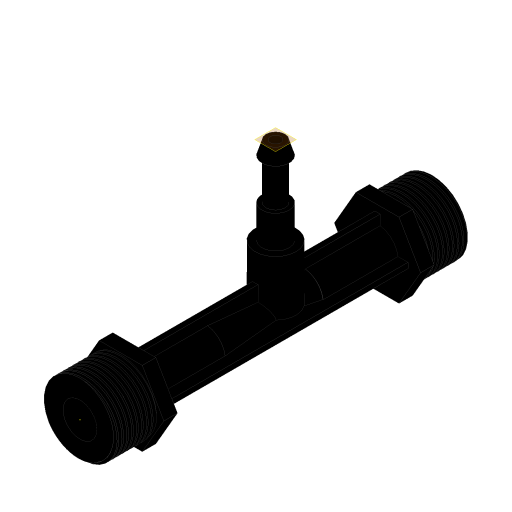
# Autodesk Inventor part: 0.75 Inch Venturi
Saved by Autodesk Inventor 2024 (Build 280153000, 153)
## iProperties
Created: 2024-08-13
Part Number: 0.75 Inch Venturi
Material: Generic
Document SubType Name: Modeling
Designer: nicme
Density: 1 g/cm^3
Appearance: Default
Author: nicme
Autodesk Inventor part; units mm, degrees
ref_plane "YZ Plane" through (0, 0, 0) normal (1, 0, 0) x (0, 1, 0)
sketch "Sketch1" plane through (0, 0, 0) normal (0, 0, 1) x (1, 0, 0)
  circle A0 centre (0, 0) radius 6.25
  circle A1 centre (0, 0) radius 13.22
  dimension "d0" = 12.5
  dimension "d1" = 26.44
  constraints: 2 centre point, 2 coincident
  measures "d0" diameter of A0
  measures "d1" diameter of A1
extrude "Extrusion1" add sketch "Sketch1" against normal blind 15
sketch "Sketch2" plane through (0, 0, 0) normal (1, 0, 0) x (0, 1, 0)
  line L0 (13.22, 0) -> (-13.22, 0) projected
  line L1 (13.22, 0) -> (12.058, 0.6049)
  line L2 (12.2284, 0.6936) -> (13.22, 1.2098)
  line L3 (13.22, 1.2098) -> (13.22, 0)
  line L4 (13.22, 0.6049) -> (11.3544, 0.6049) construction
  arc A0 (12.2284, 0.6936) -> (12.2284, 0.5162) centre (12.2746, 0.6049) ccw
  line L5 (0, 11.5896) -> (0, -31.834) construction
  point P0 (0, 0)
  dimension "d4" = 55
  dimension "d5" = 1.162
  dimension "d6" = 0.2
  constraints: 10 end point, 2 point on circle, 2 point on line, 2 tangent, 2 vertical, 1 centre point, 1 horizontal, 1 midpoint
  measures "d4" angle of L1 L2
  measures "d5" distance of L4.start L1.end
  measures "d6" diameter of A0
coil "Coil1" sketch "Sketch2" operation cut axis through (0, 0, 11.5896) along (0, 0, -1) pitch 1.814 turns 10 hand right
sketch "Sketch3" plane through (0, 0, -15) normal (0, 0, -1) x (-1, 0, 0)
  line L0 (-7.9386, 13.75) -> (7.9386, 13.75)
  line L1 (7.9386, 13.75) -> (15.8771, 0)
  line L2 (15.8771, 0) -> (7.9386, -13.75)
  line L3 (7.9386, -13.75) -> (-7.9386, -13.75)
  line L4 (-7.9386, -13.75) -> (-15.8771, 0)
  line L5 (-15.8771, 0) -> (-7.9386, 13.75)
  line L6 (-7.9386, 13.75) -> (7.9386, -13.75) construction
  line L7 (-7.9386, -13.75) -> (7.9386, 13.75) construction
  circle A0 centre (0, 0) radius 6.25
  point P0 (11.9078, 6.875)
  dimension "d15" = 27.5
  dimension "d16" = 120
  dimension "d17" = 120
  dimension "d18" = 120
  dimension "d19" = 120
  dimension "d20" = 120
  dimension "d21" = 120
  dimension "d22" = 27.5
  dimension "d24" = 27.5
  dimension "d25" = 13.75
  dimension "d26" = 13.75
  constraints: 16 end point, 2 coincident, 2 midpoint, 1 centre point, 1 horizontal, 1 parallel
  measures "d15" distance between parallel lines of L3 L0
  measures "d16" angle of L0 L5
  measures "d17" angle of L1 L0
  measures "d18" angle of L4 L5
  measures "d19" angle of L2 L1
  measures "d20" angle of L3 L4
  measures "d21" angle of L2 L3
  measures "d22" distance from line of point (11.908, 6.875) L4
  measures "d24" distance between parallel lines of L2 L5
  measures "d25" distance from line of L0 L4.end
  measures "d26" distance from line of L1 L2.end
extrude "Extrusion2" add sketch "Sketch3" along normal blind 5
sketch "Sketch4" plane through (0, 0, -20) normal (0, 0, -1) x (-1, 0, 0)
  circle A0 centre (0, 0) radius 6.2339
  circle A1 centre (0, 0) radius 7.5
  dimension "d29" = 15
  constraints: 2 centre point, 2 coincident
  measures "d29" diameter of A1
extrude "Extrusion3" add sketch "Sketch4" along normal blind 26
sketch "Sketch5" plane through (0, 0, -46) normal (0, 0, -1) x (-1, 0, 0)
  circle A0 centre (0, 0) radius 6.25
  circle A1 centre (0, 0) radius 7.5
  constraints: 2 centre point, 2 coincident
ref_plane "Work Plane1" through (0, 0, -72) normal (0, 0, -1) x (-1, 0, 0)
sketch "Sketch7" plane through (0, 0, -72) normal (0, 0, -1) x (-1, 0, 0)
  circle A0 centre (0, 0) radius 4
  circle A1 centre (0, 0) radius 5
  dimension "d39" = 8
  dimension "d40" = 10
  constraints: 2 centre point, 2 coincident
  measures "d39" diameter of A0
  measures "d40" diameter of A1
loft "Loft2" add profiles "Sketch7" section 1 edges at (7.5, 0, -46) contours A0 | A1
ref_plane "Work Plane2" through (0, 0, -82) normal (0, 0, -1) x (-1, 0, 0)
sketch "Sketch8" plane through (0, 0, -82) normal (0, 0, -1) x (-1, 0, 0)
  circle A0 centre (0, 0) radius 7.5
  constraints: 1 centre point, 1 coincident
loft "Loft3" add profiles "Sketch8" section 1 edges at (5, 0, -72)
sketch "Sketch9" plane through (0, 0, -82) normal (0, 0, -1) x (-1, 0, 0)
  circle A0 centre (0, 0) radius 7.6171
  constraints: 1 centre point, 1 coincident
extrude "Extrusion4" add sketch "Sketch9" along normal blind 27.5
sketch "Sketch10" plane through (0, 0, -109.5) normal (0, 0, -1) x (-1, 0, 0)
  line L0 (7.9386, 13.75) -> (-7.9386, 13.75) projected
  line L1 (-7.9386, 13.75) -> (-15.8771, 0) projected
  line L2 (-15.8771, 0) -> (-7.9386, -13.75) projected
  line L3 (-7.9386, -13.75) -> (7.9386, -13.75) projected
  line L4 (7.9386, -13.75) -> (15.8771, 0) projected
  line L5 (15.8771, 0) -> (7.9386, 13.75) projected
  point P0 (0, 0)
extrude "Extrusion5" add sketch "Sketch10" along normal blind 5
sketch "Sketch11" plane through (0, 0, -114.5) normal (0, 0, -1) x (-1, 0, 0)
  circle A0 centre (0, 0) radius 6.25 projected
  circle A1 centre (0, 0) radius 13.2205
  dimension "d54" = 26.441
  constraints: 1 centre point, 1 coincident
  measures "d54" diameter of A1
extrude "Extrusion6" add sketch "Sketch11" along normal blind 15
sketch "Sketch12" plane through (0, 0, 0) normal (1, 0, 0) x (0, 1, 0)
  line L0 (-13.2205, -129.5) -> (13.2205, -129.5) projected
  line L1 (13.2205, -129.5) -> (13.2205, -130.7098)
  line L2 (13.2205, -130.7098) -> (12.0585, -130.1049)
  line L3 (12.0585, -130.1049) -> (13.2205, -129.5)
  line L4 (13.2205, -130.1049) -> (11.3822, -130.1049) construction
  line L5 (0, -132.3571) -> (0, -126.5708) construction
  point P0 (0, 0)
  dimension "d57" = 55
  dimension "d58" = 1.162
  constraints: 10 end point, 2 vertical, 1 horizontal, 1 midpoint
  measures "d57" angle of L2 L3
  measures "d58" distance from line of L2.end L1
coil "Coil2" sketch "Sketch12" operation cut axis through (0, 0, -132.3571) along (0, 0, 1) pitch 1.814 turns 9 hand right
sketch "Sketch13" plane through (0, 0, -109.5) normal (0, 0, 1) x (1, 0, 0)
  line L0 (-1, -11.25) -> (1, -11.25)
  line L1 (1, -11.25) -> (1, 11.25)
  line L2 (1, 11.25) -> (-1, 11.25)
  line L3 (-1, 11.25) -> (-1, -11.25)
  circle A0 centre (0, 0) radius 6.25 projected
  line L4 (-1, -11.25) -> (1, 11.25) construction
  line L5 (1, -11.25) -> (-1, 11.25) construction
  line L6 (11.25, 1) -> (-11.25, 1)
  line L7 (-11.25, 1) -> (-11.25, -1)
  line L8 (-11.25, -1) -> (11.25, -1)
  line L9 (11.25, -1) -> (11.25, 1)
  line L10 (11.25, 1) -> (-11.25, -1) construction
  line L11 (-11.25, 1) -> (11.25, -1) construction
  point P0 (6.1695, 1)
  point P1 (6.1695, -1)
  point P2 (-1, -1)
  point P3 (-1, 1)
  point P4 (1, -1)
  point P5 (1, 1)
  dimension "d67" = 2
  dimension "d68" = 22.5
  dimension "d69" = 2
  dimension "d70" = 22.5
  constraints: 24 end point, 4 midpoint, 4 parallel, 2 horizontal, 2 perpendicular
  measures "d67" distance of L2.end L1.end
  measures "d68" distance of L8.end L7.end
  measures "d69" distance of L7.end L6.end
  measures "d70" distance between parallel lines of L0 L2
extrude "Extrusion7" add sketch "Sketch13" along normal up to surface (89.5 mm away) contours L3 A0 L1 L0 | L3 L8 L1 A0 | L8 A0 L6 L3 | L3 L6 L1 L8 | L8 L7 L6 A0 | L1 L6 A0 L8 | A0 L6 L9 L8 | L3 A0 L1 L6 | L3 L2 L1 A0
sketch "Sketch14" plane through (-1, 11.25, -109.5) normal (0, 1, 0) x (1, 0, 0)
  circle A0 centre (1, -37.5) radius 7.5
  point P0 (1, -109.5)
  dimension "d73" = 15
  constraints: 1 centre point
  measures "d73" diameter of A0
extrude "Extrusion8" add sketch "Sketch14" against normal up to surface (10.25 mm away)
sketch "Sketch15" plane through (-1, 11.25, -109.5) normal (0, 1, 0) x (1, 0, 0)
  circle A0 centre (1, -37.5) radius 7.5
  point P0 (1, -109.5)
  constraints: 1 centre point
extrude "Extrusion9" add sketch "Sketch15" along normal blind 10
sketch "Sketch16" plane through (0, 21.25, -72) normal (0, 1, 0) x (1, 0, 0)
  circle A0 centre (0, 0) radius 7.5 projected
  circle A1 centre (0, 0) radius 5
  point P0 (0, -72)
  dimension "d78" = 10
  constraints: 1 centre point, 1 coincident
  measures "d78" diameter of A1
extrude "Extrusion10" add sketch "Sketch16" along normal blind 12 contours A1
sketch "Sketch17" plane through (0, 33.25, -72) normal (0, 1, 0) x (1, 0, 0)
  circle A0 centre (0, 0) radius 3.5
  point P0 (0, -72)
  dimension "d81" = 7
  constraints: 1 centre point
  measures "d81" diameter of A0
extrude "Extrusion11" add sketch "Sketch17" along normal blind 15
sketch "Sketch18" plane through (0, 48.25, -72) normal (0, 1, 0) x (1, 0, 0)
  circle A0 centre (0, 0) radius 5
  point P0 (0, -72)
  dimension "d84" = 10
  constraints: 1 centre point
  measures "d84" diameter of A0
ref_plane "Work Plane3" through (0, 53.25, -72) normal (0, 1, 0) x (1, 0, 0)
sketch "Sketch19" plane through (0, 53.25, -72) normal (0, 1, 0) x (1, 0, 0)
  circle A0 centre (0, 0) radius 3.5
  point P0 (0, -72)
  dimension "d86" = 7
  constraints: 1 centre point
  measures "d86" diameter of A0
loft "Loft4" add profiles "Sketch18", "Sketch19"
sketch "Sketch20" plane through (0, 53.25, -72) normal (0, 1, 0) x (1, 0, 0)
  circle A0 centre (0, 0) radius 2
  point P0 (0, -72)
  dimension "d91" = 4
  constraints: 1 centre point
  measures "d91" diameter of A0
extrude "Extrusion12" cut sketch "Sketch20" against normal up to surface (52.25 mm away)
sketch "Sketch21" plane through (0, 0, 0) normal (0, 0, 1) x (1, 0, 0)
  point P0 (0, 0)
body "Solid1"
